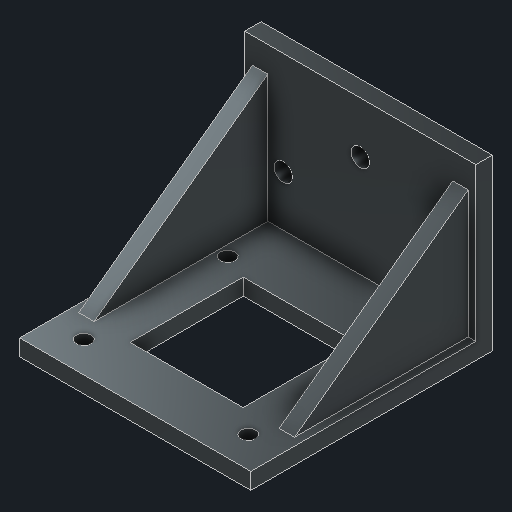
# Autodesk Inventor part: s1101mfa1016
Saved by Autodesk Inventor 2027.1 (Build 311270010, 270A)
## iProperties
Created: 2026-10-31
Part Number: s1101mfa1016
Material: Generic
Document SubType Name: Modeling
Designer: User
Density: 1 g/cm^3
Appearance: Iron Gray
Author: User
Autodesk Inventor part; units mm, degrees
ref_plane "XZ Plane" through (0, 0, 0) normal (0, 1, 0) x (-1, 0, 0)
sketch "Sketch1" plane through (0, 0, 0) normal (1, 0, 0) x (0, 1, 0)
  line L0 (0, 0) -> (41.91, 0)
  line L1 (41.91, 0) -> (41.91, 4.064)
  line L2 (41.91, 4.064) -> (4.064, 4.064)
  line L3 (4.064, 4.064) -> (4.064, 59.69)
  line L4 (4.064, 59.69) -> (0, 59.69)
  line L5 (0, 59.69) -> (0, 0)
  constraints: 12 end point
extrude "Extrusion1" add sketch "Sketch1" along normal mid plane 57.15
ref_plane "Work Plane1" through (-24.765, 0, 0) normal (1, 0, 0) x (0, 1, 0)
sketch "Sketch2" plane through (-24.765, 0, 0) normal (1, 0, 0) x (0, 1, 0)
  line L0 (4.064, 4.064) -> (35.56, 4.064)
  line L1 (35.56, 4.064) -> (4.064, 46.99)
  line L2 (4.064, 46.99) -> (4.064, 4.064)
  constraints: 6 end point
extrude "Extrusion2" add sketch "Sketch2" along normal mid plane 3.81
ref_plane "Work Plane2" through (24.765, 0, 0) normal (1, 0, 0) x (0, 1, 0)
sketch "Sketch3" plane through (24.765, 0, 0) normal (1, 0, 0) x (0, 1, 0)
  line L0 (4.064, 4.064) -> (35.56, 4.064)
  line L1 (35.56, 4.064) -> (4.064, 46.99)
  line L2 (4.064, 46.99) -> (4.064, 4.064)
  constraints: 6 end point
extrude "Extrusion3" add sketch "Sketch3" along normal mid plane 3.81
sketch "Sketch4" plane through (0, 0, 0) normal (0, 0, 1) x (1, 0, 0)
  circle A0 centre (-19.05, 16.51) radius 2.2479
  circle A1 centre (0, 29.21) radius 2.2479
  circle A2 centre (19.05, 16.51) radius 2.2479
  constraints: 3 centre point
extrude "Extrusion4" cut sketch "Sketch4" along normal mid plane 10.16
sketch "Sketch5" plane through (0, 0, 0) normal (0, 1, 0) x (-1, 0, 0)
  line L0 (13.97, 19.05) -> (-13.97, 19.05)
  line L1 (-13.97, 19.05) -> (-13.97, 46.99)
  line L2 (-13.97, 46.99) -> (13.97, 46.99)
  line L3 (13.97, 46.99) -> (13.97, 19.05)
  circle A0 centre (20.32, 16.51) radius 1.8288
  circle A1 centre (20.32, 52.07) radius 1.8288
  circle A2 centre (-20.32, 16.51) radius 1.8288
  circle A3 centre (-20.32, 52.07) radius 1.8288
  constraints: 8 end point, 4 centre point, 2 parallel, 1 horizontal, 1 perpendicular
extrude "Extrusion5" cut sketch "Sketch5" along normal mid plane 10.16
body "Solid1"
